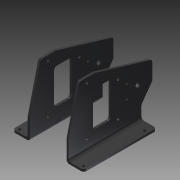
# Autodesk Inventor part: central_part
Saved by Autodesk Inventor 2015 (Build 190159000, 159)
## iProperties
Created: 2022-11-07
Part Number: central_part
Material: Generic
Document SubType Name: Modeling
Designer: Pavel Brodský
Density: 1 g/cm^3
Appearance: Default
Author: Pavel Brodský
Autodesk Inventor part; units mm, degrees
ref_plane "YZ Plane" through (0, 0, 0) normal (1, 0, 0) x (0, 1, 0)
ref_plane "XZ Plane" through (0, 0, 0) normal (0, 1, 0) x (-1, 0, 0)
sketch "Náčrt1" plane through (0, 0, 0) normal (1, 0, 0) x (0, 1, 0)
  line L0 (0, 0) -> (28, 0)
  line L1 (28, 0) -> (135, -32)
  line L2 (135, -32) -> (135, -66)
  line L3 (135, -66) -> (115, -94)
  line L4 (115, -94) -> (115, -118)
  line L5 (115, -118) -> (-20, -118)
  line L6 (-20, -118) -> (-20, -83)
  line L7 (-20, -83) -> (0, 0)
  line L8 (53, -25) -> (30, -25)
  line L9 (25, -30) -> (25, -85)
  line L10 (30, -90) -> (53, -90)
  line L11 (58, -85) -> (58, -30)
  arc A0 (58, -30) -> (53, -25) centre (53, -30) ccw
  arc A1 (30, -25) -> (25, -30) centre (30, -30) ccw
  arc A2 (25, -85) -> (30, -90) centre (30, -85) ccw
  arc A3 (53, -90) -> (58, -85) centre (53, -85) ccw
  circle A4 centre (14, -9) radius 2.5
  circle A5 centre (14, -99) radius 2.5
  circle A6 centre (72, -32) radius 2.5
  circle A7 centre (72, -96) radius 2.5
  circle A8 centre (88, -47) radius 2
  circle A9 centre (88, -72) radius 2
  circle A10 centre (108, -59.5) radius 4
  circle A11 centre (130, -59.5) radius 2
  point P0 (58, -25)
  point P1 (25, -90)
  point P2 (58, -90)
  dimension "d0" = 28
  dimension "d1" = 34
  dimension "d2" = 24
  dimension "d3" = 135
  dimension "d4" = 35
  dimension "d5" = 20
  dimension "d6" = 118
  dimension "d7" = 135
  dimension "d8" = 32
  dimension "d11" = 65
  dimension "d12" = 33
  dimension "d13" = 25
  dimension "d14" = 25
  dimension "d15" = 5
  dimension "d18" = 5
  dimension "d19" = 5
  dimension "d20" = 9
  dimension "d21" = 14
  dimension "d22" = 14
  dimension "d23" = 99
  dimension "d24" = 5
  dimension "d25" = 5
  dimension "d26" = 14
  dimension "d27" = 14
  dimension "d28" = 7
  dimension "d29" = 64
  dimension "d30" = 4
  dimension "d31" = 4
  dimension "d32" = 30
  dimension "d33" = 30
  dimension "d34" = 15
  dimension "d35" = 25
  dimension "d36" = 8
  dimension "d37" = 20
  dimension "d38" = 12.5
  dimension "d39" = 4
  dimension "d40" = 22
  constraints: 24 end point, 12 centre point, 8 point on circle, 8 tangent, 6 point on line, 4 perpendicular, 3 equal radius, 3 parallel, 2 horizontal, 1 horizontal alignment
  measures "d0" distance of L0.start L0.end
  measures "d1" distance of L1.end L2.end
  measures "d2" distance of L3.end L4.end
  measures "d3" distance of L4.end L5.end
  measures "d4" distance of L5.end L6.end
  measures "d5" horizontal distance of L0.start L6.end
  measures "d6" vertical distance of L0.start L5.end
  measures "d7" distance from line of L2 L0.start
  measures "d8" vertical distance of L1.end L0.end
  measures "d11" distance of point (58, -90) point (58, -25)
  measures "d12" distance of point (25, -90) point (58, -90)
  measures "d13" distance between parallel lines of L0 L8
  measures "d14" distance from line of L9 L0.start
  measures "d15" radius of A0
  measures "d18" diameter of A4
  measures "d19" diameter of A5
  measures "d20" distance from line of A4.centre L0
  measures "d21" horizontal distance of L0.start A4.centre
  measures "d22" horizontal distance of L0.start A5.centre
  measures "d23" distance from line of L0 A5.centre
  measures "d24" diameter of A6
  measures "d25" diameter of A7
  measures "d26" distance from line of L11 A6.centre
  measures "d27" distance from line of A7.centre L11
  measures "d28" distance from line of A6.centre L8
  measures "d29" distance of A7.centre A6.centre
  measures "d30" diameter of A8
  measures "d31" diameter of A9
  measures "d32" distance from line of L11 A8.centre
  measures "d33" distance from line of L11 A9.centre
  measures "d34" vertical distance of A8.centre A6.centre
  measures "d35" distance of A9.centre A8.centre
  measures "d36" diameter of A10
  measures "d37" horizontal distance of A9.centre A10.centre
  measures "d38" vertical distance of A10.centre A9.centre
  measures "d39" diameter of A11
  measures "d40" distance of A10.centre A11.centre
extrude "Vysunutí1" add sketch "Náčrt1" along normal blind 4 contours L0 L1 L2 L3 L4 L5 L6 L7 | A0 L11 A3 L10 A2 L9 A1 L8 | A4 | A5 | A6 | A7 | A8 | A9 | A10 | A11
extrude "Vysunutí2" cut sketch "Náčrt1" along normal through all contours A0 L11 A3 L10 A2 L9 A1 L8 | A4 | A5 | A6 | A7 | A8 | A9 | A10
ref_plane "Pracovní rovina1" through (-34, 0, 0) normal (1, 0, 0) x (0, 0, -1)
sketch "Náčrt2" plane through (0, -20, -118) normal (0, 0, -1) x (-1, 0, 0)
  line L0 (0, 135) -> (-32, 135)
  line L1 (-32, 135) -> (-32, 0)
  line L2 (-32, 0) -> (0, 0)
  line L3 (0, 0) -> (0, 135)
  circle A0 centre (-25, 120) radius 2.5
  circle A1 centre (-25, 6) radius 2.5
  point P0 (0, 20)
  dimension "d42" = 32
  dimension "d43" = 5
  dimension "d44" = 5
  dimension "d45" = 7
  dimension "d46" = 6
  dimension "d47" = 114
  constraints: 8 end point, 2 centre point, 2 coincident, 2 parallel, 1 horizontal, 1 perpendicular, 1 vertical alignment
  measures "d42" distance between parallel lines of L1 L3
  measures "d43" diameter of A0
  measures "d44" diameter of A1
  measures "d45" distance from line of L1 A0.centre
  measures "d46" distance from line of L2 A1.centre
  measures "d47" distance of A1.centre A0.centre
extrude "Vysunutí3" add sketch "Náčrt2" along normal blind 4
fillet "Zaoblení1" radius 5 10 edges at (0, 47.5, -122) (4, 47.5, -118) (32, 115, -120) (32, -20, -120) (2, -20, -83) (2, 0, 0) (2, 28, 0) (2, 135, -32) (2, 135, -66) (2, 115, -94)
mirror "Zrcadlit2" about plane through (-34, 0, 0) normal (1, 0, 0) of "Vysunutí1", "Vysunutí2", "Vysunutí3", "Zaoblení1"
equation "\"d19\" = d18"
equation "\"d22\" = d21"
equation "\"d25\" = d24"
equation "\"d27\" = d26"
equation "\"d31\" = d30"
equation "\"d33\" = d32"
equation "\"d38\" = 0.5 * d35"
equation "\"d39\" = d30"
equation "\"d44\" = d43"
